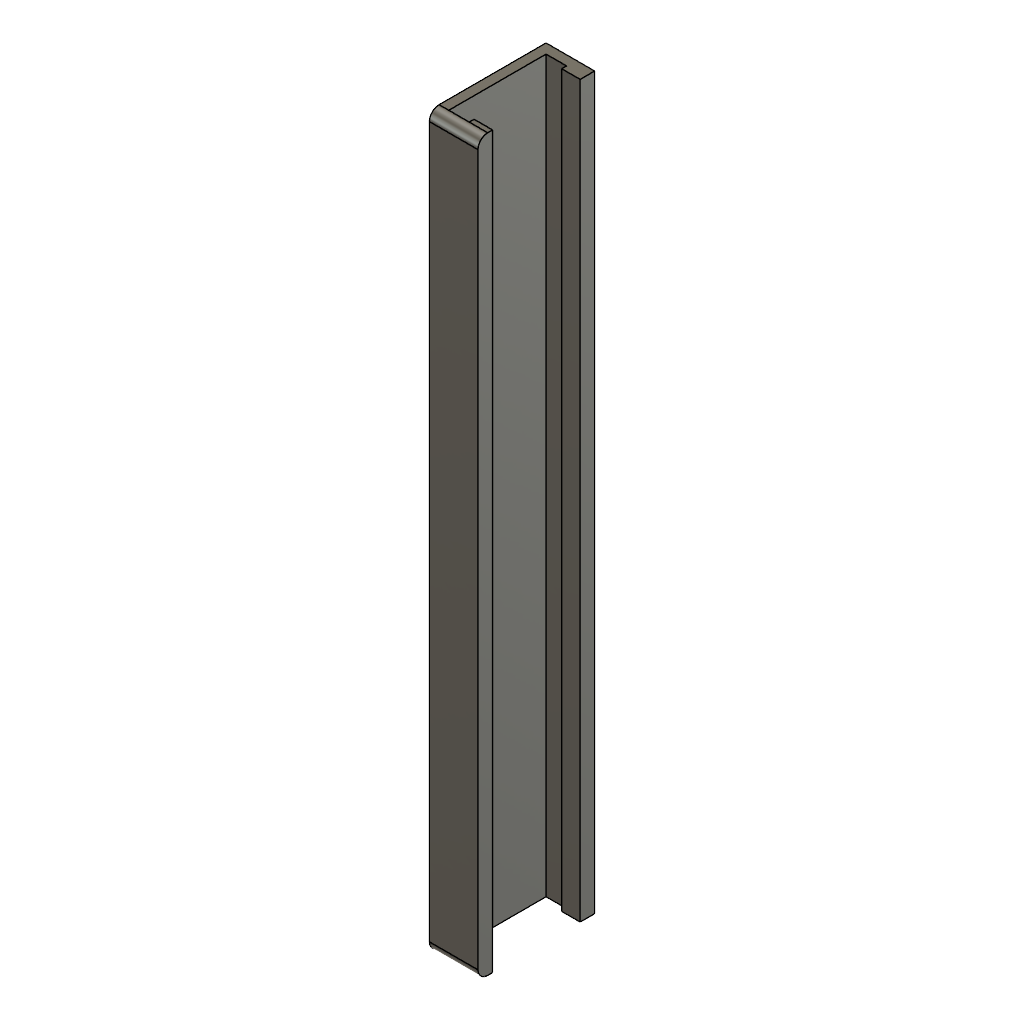
02-35_케이블커버 (Autodesk Fusion 360 design; units mm, degrees)
Autodesk Fusion 360 part; units mm, degrees
sketch "스케치1" plane through (0, 0, 0) normal (0, 1, 0) x (1, 0, 0)
  line L0 (0, 0) -> (-10, 0)
  line L1 (-10, 0) -> (-10, 24)
  line L2 (-10, 24) -> (0, 24)
  line L3 (0, 24) -> (0, 21)
  line L4 (0, 21) -> (-3.8, 21)
  line L5 (-3.8, 21) -> (-3.8, 22)
  line L6 (-3.8, 22) -> (-8, 22)
  line L7 (-10, 12) -> (0, 12) construction
  line L8 (0, 0) -> (0, 3)
  line L9 (-3.8, 3) -> (-3.8, 2)
  line L10 (-3.8, 2) -> (-8, 2)
  line L11 (0, 3) -> (-3.8, 3)
  line L12 (-8, 22) -> (-8, 2)
  dimension "d1" = 10
  dimension "d2" = 24
  dimension "d3" = 3
  dimension "d4" = 3.8
  dimension "d5" = 1
  constraint coincident L0.start L8.start
  constraint horizontal L0
  constraint perpendicular L0 L1
  constraint perpendicular L1 L2
  constraint perpendicular L2 L3
  constraint perpendicular L3 L4
  constraint perpendicular L2 L5
  constraint perpendicular L5 L6
  constraint midpoint L1 L7.start
  constraint perpendicular L1 L7
  constraint symmetric L2.end L7 L0.start
  constraint symmetric L3.end L7 L8.end
  constraint symmetric L4.end L7 L9.start
  constraint symmetric L5.end L7 L9.end
  constraint symmetric L6.end L7 L10.end
  measures "d1" distance of L0.start L0.end
  measures "d2" distance of L0.end L1.end
  measures "d3" distance of L2.end L3.end
  measures "d4" distance of L3.end L4.end
  measures "d5" distance of L4.end L5.end
extrude "돌출1" add sketch "스케치1" along normal blind 150
fillet "필렛1" radius 2 2 edges at (-5, 150, 0) (-5, 0, 0)
